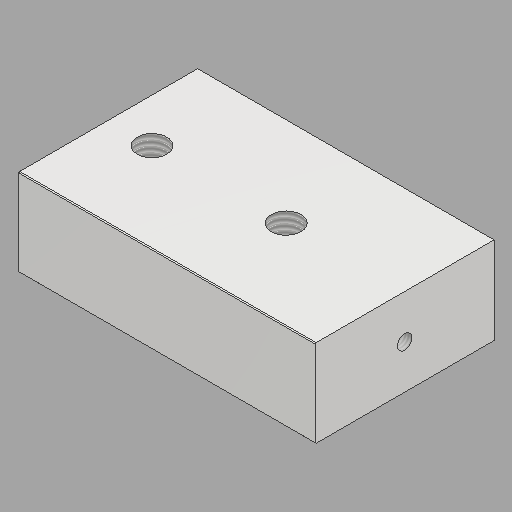
# Autodesk Inventor part: BT021_thutrn22_26
Saved by Autodesk Inventor 2025.3 (Build 293356000, 356)
## iProperties
Company: HTBLA Kaindorf
RuleStatus: InUse
Created: 2026-08-19
Part Number: BT021_thutrn22_26
Project: Biegeroboter
Material: ABS-Kunststoff
Description: distanzleiste
Document SubType Name: Modeling
Designer: thutrn22
Density: 1.06 g/cm^3
Appearance: Glatt - Weiß
Mass: 53.5773 g
Surface Area: 102.222 cm^2
Volume: 50.5446 cm^3
AfterDocNew0: iProperties-Editor_aufrufen
Author: trist
Keywords: 2026
Autodesk Inventor part; units mm, degrees
ref_plane "YZ Plane" through (0, 0, 0) normal (1, 0, 0) x (0, 1, 0)
ref_plane "XZ Plane" through (0, 0, 0) normal (0, 1, 0) x (-1, 0, 0)
ref_plane "XY Plane" through (0, 0, 0) normal (0, 0, 1) x (1, 0, 0)
sketch "Skizze3" plane through (0, 0, 0) normal (0, 0, 1) x (1, 0, 0)
  line L0 (-28, 0) -> (28, 0) projected
  line L1 (0, -42.3) -> (0, 50.8) projected
  line L2 (20, 29) -> (20, -29)
  line L3 (20, -29) -> (-20, -29)
  line L4 (-20, -29) -> (-20, 29)
  line L5 (-20, 29) -> (-20, 37.5)
  line L6 (-20, 37.5) -> (20, 37.5)
  line L7 (20, 37.5) -> (20, 29)
  point P0 (0, 0)
  point P1 (0, -29)
  point P2 (20, 0)
  dimension "d4" = 40
  dimension "d41" = 66.5
  constraints: 12 end point, 2 vertical, 1 perpendicular, 1 other
  measures "d4" distance of L2.end L3.end
  measures "d41" distance between parallel lines of L6 L3
extrude "Extrusion3" add sketch "Skizze3" along normal blind 19.5
sketch "Skizze4" plane through (0, 0, 19.5) normal (0, 0, 1) x (1, 0, 0)
  line L0 (-28, 0) -> (28, 0) projected
  line L1 (0, -42.3) -> (0, 50.8) projected
  line L2 (-20, -29) -> (20, -29) projected
  point P0 (0, 0)
  point P1 (0, 11)
  point P2 (0, -19)
  dimension "d35" = 10
  dimension "d36" = 30
  constraints: 2 point on line
  measures "d35" distance from line of L2 point (0, -19)
  measures "d36" distance of point (0, -19) point (0, 11)
hole "Bohrung2" at (0, 11, 19.5) at (0, -19, 19.5) direction (0, 0, -1) diameter 6.647 depth 15 tip angle 118 thread size "M8x1.25" class "6H" standard "ISO Metric profile"
sketch "Skizze5" plane through (0, 0, 19.5) normal (0, 0, 1) x (1, 0, 0)
  line L0 (0, -42.3) -> (0, 50.8) projected
  line L1 (-28, 0) -> (28, 0) projected
  line L2 (-20, -29) -> (20, -29) projected
  point P0 (0, 0)
  point P1 (0, -19)
  dimension "d37" = 10
  measures "d37" distance from line of L2 point (0, -19)
hole "Bohrung3" at (0, -19, 19.5) direction (0, 0, -1) diameter 6.647 end through all thread size "M8x1.25" class "6H" standard "ISO Metric profile"
chamfer "Fasen1" distance 0.2 angle 45 6 edges at (20, 4.25, 19.5) (0, -29, 19.5) (20, 4.25, 0) (20, -29, 9.75) (0, -29, 0) (-20, -29, 9.75)
sketch "Skizze6" plane through (-20, 37.5, 19.5) normal (0, 1, 0) x (1, 0, 0)
  line L0 (0, 19.5) -> (0, 0) projected
  line L1 (39.8, 0) -> (0, 0) projected
  point P0 (20, 19.5)
  point P1 (20, 9.75)
  dimension "d43" = 9.75
  dimension "d44" = 20
  measures "d43" distance from line of L1 point (20, 9.75)
  measures "d44" distance from line of L0 point (20, 9.75)
hole "Bohrung4" at (0, 37.5, 9.75) direction (0, -1, 0) diameter 3.242 depth 11.8 tip angle 118 thread size "M4x0.7" class "6H" standard "ISO Metric profile"
